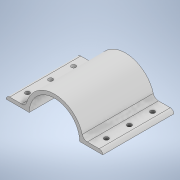
# Autodesk Inventor part: manson teava_astupare_gaura
Saved by Autodesk Inventor 2020 (Build 240168000, 168)
## iProperties
Created: 2023-12-23
Part Number: manson teava_astupare_gaura
Material: Generic
Document SubType Name: Sheet Metal
Designer: user
Density: 1 g/cm^3
Sheet Metal Rule: Default_mm
Appearance: Default
Author: user
Autodesk Inventor part; units mm, degrees
ref_plane "YZ Plane" through (0, 0, 0) normal (1, 0, 0) x (0, 1, 0)
ref_plane "XZ Plane" through (0, 0, 0) normal (0, 1, 0) x (-1, 0, 0)
ref_plane "XY Plane" through (0, 0, 0) normal (0, 0, 1) x (1, 0, 0)
sketch "Sketch1" plane through (0, 0, 0) normal (0, 0, 1) x (1, 0, 0)
  arc A0 (14.1994, 0.1316) -> (-14.1994, 0.1316) centre (0, 0) ccw
  line L0 (-16.1995, 0.1316) -> (-27.1913, 0.1316)
  line L1 (-27.1913, 0.1316) -> (-27.1913, 2.1316)
  line L2 (-27.1913, 2.1316) -> (-16.0592, 2.1316)
  line L3 (0, 0) -> (0, 19.4043)
  line L4 (16.1995, 0.1316) -> (27.1913, 0.1316)
  line L5 (27.1913, 0.1316) -> (27.1913, 2.1316)
  line L6 (27.1913, 2.1316) -> (16.0592, 2.1316)
  arc A1 (16.1995, 0.1316) -> (-16.1995, 0.1316) centre (0, 0) ccw
  line L7 (-27.1913, 0.1316) -> (-14.1994, 0.1316)
  line L8 (27.1913, 0.1316) -> (14.1994, 0.1316)
  dimension "d0" = 28.4
  dimension "d2" = 2
  dimension "d3" = 32.4
  dimension "d4" = 11.1321
  constraints: 18 end point, 6 point on circle, 2 centre point, 2 coincident, 2 horizontal, 2 point on line, 2 symmetric about line, 1 collinear, 1 parallel, 1 perpendicular, 1 vertical
  measures "d0" diameter of A0
  measures "d2" distance of L0.end L1.end
  measures "d3" diameter of A1
  measures "d4" distance of L1.end L2.end
extrude "Extrusion1" add sketch "Sketch1" along normal blind 40
fillet "Fillet1" radius 3 2 edges at (-16.0592, 2.1316, 20) (16.0592, 2.1316, 20)
sketch "Sketch2" plane through (-27.1913, 2.1316, 40) normal (0, 1, 0) x (1, 0, 0)
  line L0 (8.6898, 40) -> (8.6898, 0) projected
  line L1 (8.6898, 40) -> (0, 40) projected
  line L2 (0, 40) -> (0, 0) projected
  line L3 (8.6898, 0) -> (0, 0) projected
  line L4 (45.6928, 0) -> (45.6928, 40) projected
  line L5 (54.3826, 0) -> (45.6928, 0) projected
  line L6 (54.3826, 40) -> (54.3826, 0) projected
  line L7 (54.3826, 40) -> (45.6928, 40) projected
  line L8 (27.1913, 40) -> (27.1913, 0)
  line L9 (41.3907, 0) -> (12.9919, 0) projected
  line L10 (27.1913, -7.2763) -> (27.1913, 51.2088)
  circle A0 centre (4.9898, 33) radius 1.25
  circle A1 centre (4.9898, 20) radius 1.25
  circle A2 centre (4.9898, 7) radius 1.25
  line L11 (45.6928, 40) -> (45.6928, 0)
  line L12 (45.6928, 40) -> (54.3826, 40)
  line L13 (54.3826, 40) -> (54.3826, 0)
  line L14 (45.6928, 0) -> (54.3826, 0)
  circle A3 centre (49.3928, 33) radius 1.25
  circle A4 centre (49.3928, 20) radius 1.25
  circle A5 centre (49.3928, 7) radius 1.25
  dimension "d8" = 40
  dimension "d9" = 20
  dimension "d10" = 7
  dimension "d11" = 33
  dimension "d12" = 2.5
  dimension "d13" = 2.5
  dimension "d14" = 2.5
  dimension "d18" = 3.7
  dimension "d19" = 3.7
  dimension "d20" = 3.7
  constraints: 12 end point, 6 centre point, 6 coincident, 6 symmetric about line, 2 point on line, 1 midpoint, 3 other
  measures "d8" distance of L1.end L2.end
  measures "d9" distance from line of L3 point (4.99, 20)
  measures "d10" distance from line of L3 point (4.99, 7)
  measures "d11" distance from line of L3 point (4.99, 33)
  measures "d12" diameter of A0
  measures "d13" diameter of A1
  measures "d14" diameter of A2
  measures "d18" distance from line of L0 A0.centre
  measures "d19" distance from line of L0 point (4.99, 20)
  measures "d20" distance from line of L0 point (4.99, 7)
extrude "Extrusion2" cut sketch "Sketch2" against normal blind 40 contours A0 | A1 | A2 | A3 | A4 | A5
fillet "Fillet2" radius 2 2 edges at (27.1913, 2.1316, 20) (-27.1913, 2.1316, 20)
equation "\"d19\" = d18"
equation "\"d20\" = d18"
equation "\"BendRadius\" = Thickness"
equation "\"BendReliefWidth\" = Thickness"
equation "\"BendReliefDepth\" = 0.5 * Thickness"
equation "\"CornerReliefSize\" = 4 * Thickness"
equation "\"MinimumRemnant\" = 2 * Thickness"
equation "\"TransitionRadius\" = BendRadius"
equation "\"JacobiRadiusSize\" = BendRadius"
equation "\"GapSize\" = Thickness"
equation "\"Thickness\" = 0.5"
body "Solid1"
